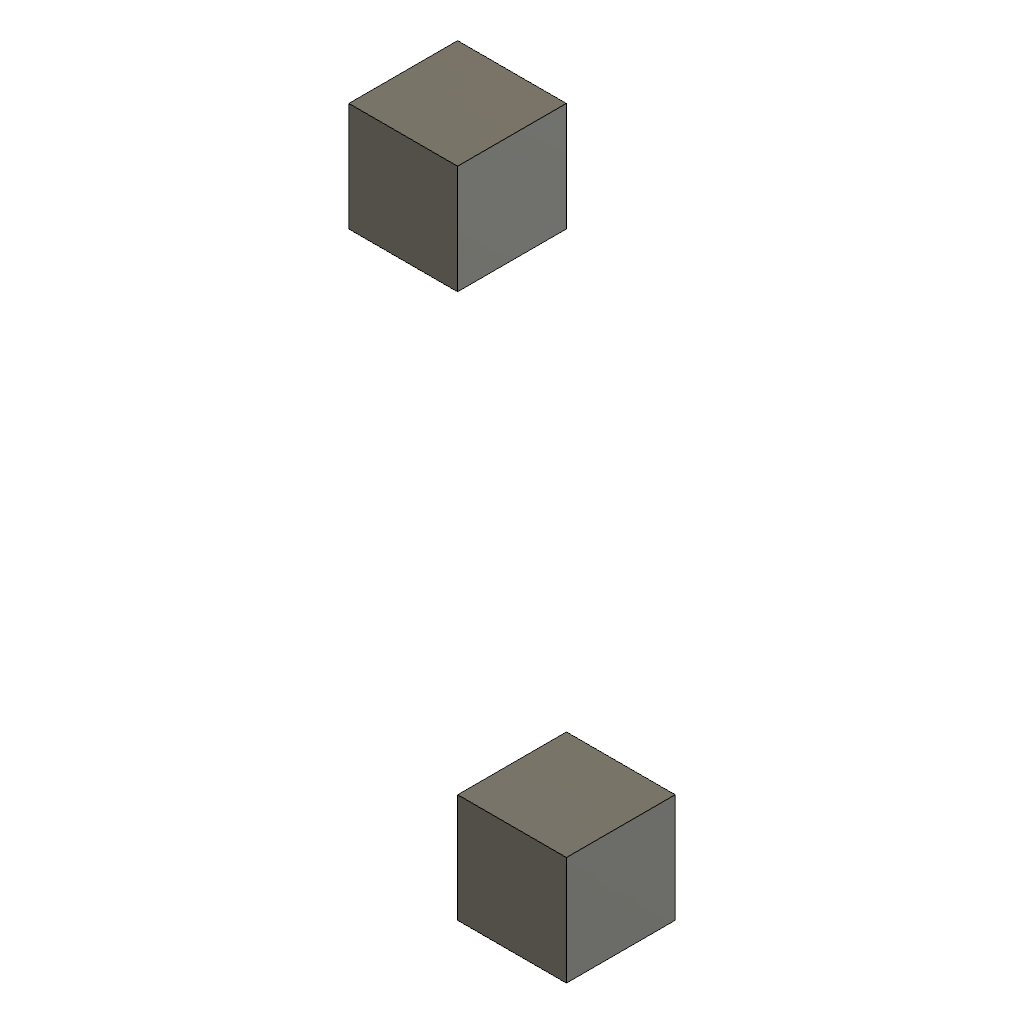
root_suppressed (Autodesk Fusion 360 design; units mm, degrees)
part number: 2026-10-21-12-03-32-439
part number: 2026-10-21-12-03-32-627
part number: 2026-10-21-12-03-32-638
Autodesk Fusion 360 part; units mm, degrees
sketch "RigidGroupFirstProfile" plane through (0, 0, 0) normal (0, 0, 1) x (1, 0, 0) in component "RigidGroupFirst"
  line L0 (0, 0) -> (10, 0)
  line L1 (10, 0) -> (10, 10)
  line L2 (10, 10) -> (0, 10)
  line L3 (0, 10) -> (0, 0)
extrude "RigidGroupFirstExtrude" add sketch "RigidGroupFirstProfile" along normal blind 10 makes body 1 in component "RigidGroupFirst"
sketch "RigidGroupSecondProfile" plane through (0, 0, 0) normal (0, 0, 1) x (1, 0, 0) in component "RigidGroupSecond"
  line L0 (0, 0) -> (10, 0)
  line L1 (10, 0) -> (10, 10)
  line L2 (10, 10) -> (0, 10)
  line L3 (0, 10) -> (0, 0)
extrude "RigidGroupSecondExtrude" add sketch "RigidGroupSecondProfile" along normal blind 10 separate body makes body 2 in component "RigidGroupSecond"
component "RigidGroupFirst" placed x (1, 0, 0) y (0, 1, 0) z (0, 0, 1) at (10, 20, 0)
component "RigidGroupSecond" placed x (1, 0, 0) y (0, 1, 0) z (0, 0, 1) at (40, -10, 20)
named bodies: "RigidGroupFirstBody", "RigidGroupSecondBody"
